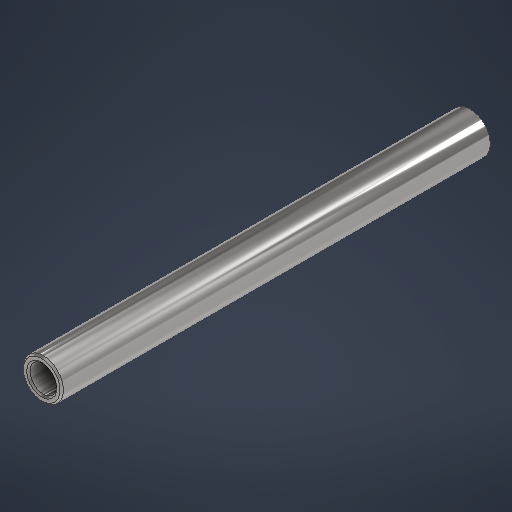
# Autodesk Inventor part: drive_shaft_center
Saved by Autodesk Inventor 2027.1 (Build 311270010, 270A)
## iProperties
Created: 2026-10-07
Part Number: drive_shaft_center
Material: Stainless Steel
Document SubType Name: Modeling
Designer: luca
Density: 8 g/cm^3
Appearance: Stahl - poliert
Mass: 64.277 g
Surface Area: 81.4974 cm^2
Volume: 8.03462 cm^3
Author: luca
Autodesk Inventor part; units mm, degrees
ref_plane "YZ Plane" through (0, 0, 0) normal (1, 0, 0) x (0, 1, 0)
ref_plane "XZ Plane" through (0, 0, 0) normal (0, 1, 0) x (-1, 0, 0)
ref_plane "XY Plane" through (0, 0, 0) normal (0, 0, 1) x (1, 0, 0)
sketch "Skizze1" plane through (0, 0, 0) normal (0, 1, 0) x (-1, 0, 0)
  circle A0 centre (0, 0) radius 6
  circle A1 centre (0, 0) radius 4
  dimension "d0" = 12
  dimension "d1" = 8
  constraints: 2 centre point, 2 coincident
  measures "d0" diameter of A0
  measures "d1" diameter of A1
extrude "Extrusion1" add sketch "Skizze1" along normal blind 128
chamfer "Chamfer1" distance 0.5 angle 45 2 edges at (6, 0, 0) (4, 0, 0)
